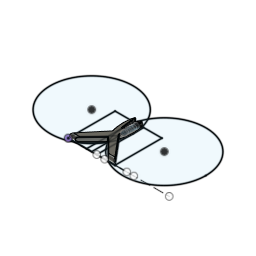
probe_holder-v9 (Autodesk Fusion 360 design; units mm, degrees)
Autodesk Fusion 360 part; units mm, degrees
sketch "Sketch1" plane through (0, 0, 0) normal (0, 0, 1) x (1, 0, 0)
  line L0 (0, 0) -> (100, 0)
  line L1 (100, 0) -> (100, 100)
  line L2 (100, 100) -> (0, 100)
  line L3 (0, 100) -> (0, 0)
  circle A0 centre (50, 100) radius 6
  circle A1 centre (50, 94) radius 5.5
  line L4 (50, 100) -> (50, 0)
  line L5 (0, 0) -> (139.9907, 0) construction
  line L6 (100, 0) -> (215.4701, 0) construction
  line L7 (75, 0) -> (125, 0) construction
  line L8 (15, 0) -> (50, 35)
  line L9 (15, 0) -> (85, 0) construction
  line L10 (85, 0) -> (50, 35)
  line L11 (85, 0) -> (100, 0)
  circle A2 centre (50, 88.5) radius 5
  circle A3 centre (50, 83.5) radius 4.5
  circle A4 centre (50, 79) radius 4
  circle A5 centre (50, 75) radius 3.5
  circle A6 centre (50, 71.5) radius 3
  circle A7 centre (50, 68.5) radius 2.5
  line L12 (42.5, 100) -> (50, 100)
  line L13 (50, 100) -> (55, 100)
  circle A8 centre (-27.5351, 77.5351) radius 88.436
  circle A9 centre (127.5351, 77.5351) radius 88.436
  line L14 (50, 100) -> (58, 100)
  line L15 (50, 100) -> (42, 100)
  line L16 (39.0991, 100) -> (39.0991, 0)
  line L17 (60.9009, 100) -> (60.9009, 0)
  line L18 (0, 0) -> (50, 59.5877)
  line L19 (0, 0) -> (77.7862, 0) construction
  line L20 (100, 0) -> (50, 59.5877)
  dimension "d1" = 100
  dimension "d2" = 100
  dimension "d3" = 12
  dimension "d4" = 11
  dimension "d11" = 45
  dimension "d12" = 15
  dimension "d13" = 15
  dimension "d14" = 10
  dimension "d15" = 9
  dimension "d16" = 8
  dimension "d17" = 7
  dimension "d18" = 6
  dimension "d19" = 5
  dimension "d109" = 8
  dimension "d110" = 8
  dimension "d114" = 50
  constraint horizontal L0
  constraint vertical L1
  constraint horizontal L2
  constraint vertical L3
  constraint coincident L0.start L3.end
  constraint midpoint L2 A0.centre
  constraint coincident A0 A1.centre
  constraint coincident A0.centre L4.start
  constraint midpoint L0 L4.end
  constraint horizontal L5
  constraint horizontal L6
  constraint horizontal L7
  constraint coincident L5 L7.start
  constraint horizontal L9
  constraint coincident L0 L8.start
  constraint coincident L4 L8.end
  constraint coincident A1 A2.centre
  constraint coincident L4 A2.centre
  constraint coincident A2 A3.centre
  constraint coincident L4 A3.centre
  constraint coincident L4 A4.centre
  constraint coincident A3 A4.centre
  constraint coincident L4 A5.centre
  constraint coincident A4 A5.centre
  constraint coincident A5 A6.centre
  constraint coincident L4 A6.centre
  constraint coincident A6 A7.centre
  constraint coincident L4 A7.centre
  constraint coincident L2 L12.start
  constraint coincident L2 A0.centre
  constraint perpendicular L4 L12
  constraint coincident L12 L13.end
  constraint parallel L12 L13
  constraint coincident L8.end A8
  constraint coincident L8.start A8
  constraint coincident L9.end A9
  constraint coincident L8.end A9
  constraint perpendicular L4 L14
  constraint parallel L2 L15
  constraint coincident A8 L14.end
  constraint coincident A9 L15.end
  constraint vertical L16
  constraint coincident L2 L16.start
  constraint coincident L5 L16.end
  constraint tangent A9 L16
  constraint coincident L2 L17.start
  constraint perpendicular L2 L17
  constraint tangent A8 L17
  constraint horizontal L19
  constraint coincident L4 L18.end
  measures "d1" distance of L0.start L2.end
  measures "d2" distance of L0.start L0.end
  measures "d3" diameter of A0
  measures "d4" diameter of A1
  measures "d11" angle of L8 L9
  measures "d12" distance of L0.start L8.start
  measures "d13" distance of L0.end L9.end
  measures "d14" diameter of A2
  measures "d15" diameter of A3
  measures "d16" diameter of A4
  measures "d17" diameter of A5
  measures "d18" diameter of A6
  measures "d19" diameter of A7
  measures "d109" distance of A0.centre L14.end
  measures "d110" distance of A0.centre L15.end
  measures "d114" angle of L18 L19
extrude "Extrude1" add sketch "Sketch1" along normal blind 10 contours L0 L8 L16 L18 | L8 A9 L16 L18 | L2 A0 A1 L4 A2 A3 A4 A5 A6 A7 L12 A9 L15 L18 | L4 A9 L18 | L10 A8 L17 L20 | L4 A8 L20 | L2 A0 A1 L4 A2 A3 A4 A5 A6 A7 A8 L14 L20 | L0 L10 L11 L17 L20
fillet "Fillet18" radius 1 3 edges at (50, 35, 5) (43.0708, 51.3298, 5) (56.9292, 51.3298, 5)
fillet "Fillet16" radius 5 4 edges at (7.5, 0, 10) (7.5, 0, 0) (92.5, 0, 10) (92.5, 0, 0)
fillet "Fillet17" radius 1 8 faces at (37.3378, 30.0684, 0) (14.4148, 4.6812, 0.0101) (5, 0, 4.9997) (14.4148, 4.6812, 9.9899) (37.3378, 30.0684, 10) (14.4148, 4.6812, 0.0101) (5, 0, 4.9997) (14.4148, 4.6812, 9.9899)
